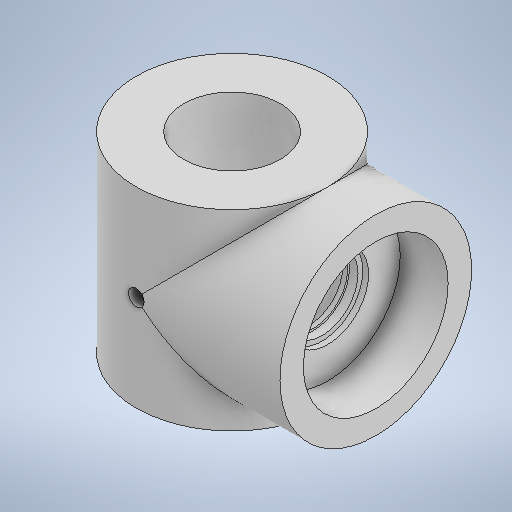
# Autodesk Inventor part: 外轴承支架
Saved by Autodesk Inventor 2025 (Build 290162000, 162)
## iProperties
Created: 2026-11-18
Part Number: 外轴承支架
Material: 常规
Document SubType Name: Modeling
Designer: ylh00
Density: 1 g/cm^3
Appearance: 默认
Author: ylh00
Autodesk Inventor part; units mm, degrees
ref_plane "XZ Plane" through (0, 0, 0) normal (0, 1, 0) x (-1, 0, 0)
ref_plane "XY Plane" through (0, 0, 0) normal (0, 0, 1) x (1, 0, 0)
sketch "草图1" plane through (0, 0, 0) normal (0, 1, 0) x (-1, 0, 0)
  circle A0 centre (0, 0) radius 10.1
  circle A1 centre (0, 0) radius 20
  dimension "d0" = 20.2
  dimension "d1" = 40
  constraints: 2 centre point, 2 coincident
  measures "d0" diameter of A0
  measures "d1" diameter of A1
extrude "拉伸1" add sketch "草图1" along normal blind 40
sketch "草图2" plane through (0, 0, 0) normal (0, 0, 1) x (1, 0, 0)
  line L0 (-20, 0) -> (-20, 40) projected
  line L1 (-20, 20) -> (20, 20)
  line L2 (20, 0) -> (20, 40) projected
  circle A0 centre (0, 20) radius 1.65
  point P0 (0, 0)
  dimension "d4" = 3.3
  constraints: 3 midpoint, 2 end point, 1 centre point
  measures "d4" diameter of A0
extrude "拉伸2" cut sketch "草图2" along normal mid plane 50
ref_plane "工作平面1" through (20, 0, 0) normal (1, 0, 0) x (0, 1, 0)
sketch "草图7" plane through (20, 0, 0) normal (1, 0, 0) x (0, 1, 0)
  circle A0 centre (20, 0) radius 20
  point P0 (0, 0)
  constraints: 1 horizontal alignment, 2 other
extrude "拉伸3" add sketch "草图7" along normal blind 10 and the other way blind 20
sketch "草图8" plane through (0, 40, 0) normal (0, 1, 0) x (1, 0, 0)
  circle A0 centre (0, 0) radius 10.1
  constraints: 1 centre point, 1 coincident
extrude "拉伸4" cut sketch "草图8" against normal blind 50
sketch "草图9" plane through (0, 0, 0) normal (0, 0, 1) x (1, 0, 0)
  line L0 (0, 21.65) -> (0, 18.35) projected
  circle A0 centre (0, 20) radius 1.65
  point P0 (0, 0)
  constraints: 1 midpoint, 1 vertical alignment, 2 other
extrude "拉伸5" cut sketch "草图9" along normal mid plane 50
sketch "草图10" plane through (30, 20, 0) normal (1, 0, 0) x (0, 0, -1)
  circle A0 centre (0, 0) radius 15.1
  point P0 (0, -20)
  dimension "d17" = 30.2
  constraints: 1 centre point
  measures "d17" diameter of A0
extrude "拉伸6" cut sketch "草图10" against normal blind 10
sketch "草图11" plane through (20, 20, 0) normal (1, 0, 0) x (0, 0, -1)
  circle A0 centre (0, 0) radius 7.1
  point P0 (0, -20)
  dimension "d20" = 14.2
  constraints: 1 centre point
  measures "d20" diameter of A0
extrude "拉伸7" cut sketch "草图11" against normal blind 4
sketch "草图12" plane through (20, 20, 0) normal (1, 0, 0) x (0, 0, -1)
  circle A0 centre (0, 0) radius 7.1 projected
  circle A1 centre (0, 0) radius 7.5
  point P0 (0, -20)
  dimension "d23" = 15
  constraints: 1 centre point, 1 coincident
  measures "d23" diameter of A1
extrude "拉伸8" cut sketch "草图12" against normal blind 3 contours A0 | A1
sketch "草图13" plane through (20, 20, 0) normal (1, 0, 0) x (0, 0, -1)
  circle A0 centre (0, 0) radius 8.5
  point P0 (0, -20)
  dimension "d26" = 17
  constraints: 1 centre point
  measures "d26" diameter of A0
extrude "拉伸9" cut sketch "草图13" against normal blind 1.2
